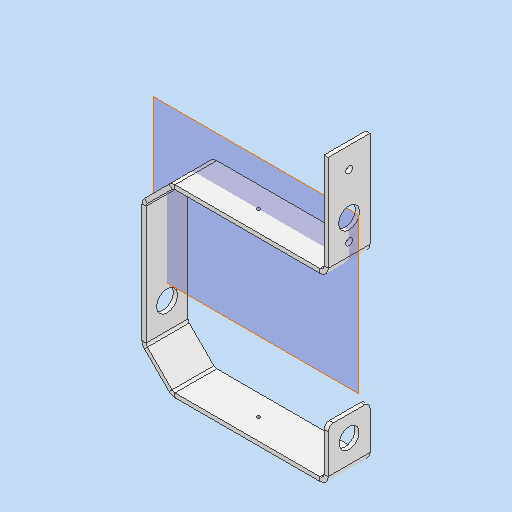
# Autodesk Inventor part: SE0004AN000_G01_106
Saved by Autodesk Inventor 2023.3 (Build 273359000, 359)
## iProperties
RuleStatus: InUse
Created: 2021-06-29
Part Number: SE0004AN000_G01_106
Material: 1.0330 DC01
Description: =<RBPARTNOTITLE2>
Document SubType Name: Blech
Designer: frt9bw
Mass: 758.691 g
Surface Area: 546.469 cm^2
Volume: 96.6485 cm^3
Density: 7.85 g/cm^3
Sheet Metal Rule: Standard_mm
Appearance: weiss AnP
Flat Pattern Width: 4 cm
Flat Pattern Length: 62.7681 cm
Flat Pattern Area: 251.073 cm^2
Sheet Metal Width: 40,000 mm
Sheet Metal Length: 627,681 mm
Sheet Metal Area: 25107,259 mm^2
Vendor: ASW
AnP_Kategorie: 1
AnP_Material: =<Material>
MaxAbmaße: 212,569 x 40 x 178,284 (FM)
AnP_TemplVers: 20200821
RBDOCUMENTTYPE: DRF
RBDOCUMENTVERSION: 00
RBDRAWINGMAINSCALE: 1:1
RBDRAWINGMISSINGSPEC: --
RBDRAWINGVOLUME: --
RBDSV1: 0850
RBGBEDGESIN1: +0,5
RBGBEDGESIN2: +0,2
RBGBEDGESOUT1: -0,3
RBGBEDGESOUT2: -0,1
RBMATERIAL: =<Material>
RBMATMEETS: --
RBMATNO: =<Part Number>
RBPARTMADEOF: 212,569 x 40 x 178,284 (FM)
RBPARTNO: SIEHE MNR
RBPARTNOTITLE1: manufactured part
RBPARTNOTITLE2: Anfertigungsteil
RBPARTSAFETYINDICATOR: --
RBSURFACE: powder-coated RAL9016, IGP-Dura mix 331SA90160C00
RBSURFACE2: pulverbeschichtet RAL9016, IGP-Dura mix 331SA90160C00
RBZEDGESNORM: ISO13715:2002-06
RBZGENDIMCLASS: m
RBZGENDIMNORM: ISO 2768-1:1989-11
RBZGENGEOCLASS: H
RBZGENGEONORM: ISO 2768-2:1989-11
RBZSURFACENORM: ISO13D2:2002-02
RBZTOLERANCENORM: ISO 14405-1:2010-12
Author: frt9bw
Keywords: =<RBPARTMADEOF>
Comments: =<RBSURFACE2>
Revision Number: 01
Autodesk Inventor part; units mm, degrees
ref_plane "YZ Plane" through (0, 0, 0) normal (1, 0, 0) x (0, 1, 0)
ref_plane "XY Plane" through (0, 0, 0) normal (0, 0, 1) x (1, 0, 0)
sketch "Skizze1" plane through (0, 0, 0) normal (0, 0, 1) x (1, 0, 0)
  line L0 (0, 0) -> (150, 0)
  line L1 (150, 0) -> (150, 40)
  line L2 (150, 40) -> (0, 40)
  line L3 (0, 40) -> (0, 0)
  dimension "d0" = 150
  dimension "d1" = 40
  measures "d0" distance of L1.end L2.end
  measures "d1" distance of L2.end L0.start
extrude "Grobblech1" add sketch "Skizze1" along normal blind 4
sketch "Skizze2" plane through (146, 40, 0) normal (1, 0, 0) x (0, 1, 0)
  line L0 (-40, 0) -> (0, 0)
  line L1 (0, 0) -> (0, 100)
  line L2 (0, 100) -> (-40, 100)
  line L3 (-40, 100) -> (-40, 0)
  constraints: 6 end point, 1 horizontal, 1 perpendicular, 1 vertical
edge flange "Lasche1" height 100 angle 90 thickness 4 bend radius 4 thickness toward (1, 0, 0) relief tear relief width 4 relief depth 2 edges at (150, 20, 4) wall of the first edge with corners at (146, 0, 0) (146, 40, 0) (146, 40, 100) (146, 0, 100)
bend "Biegung1"
corner "Ecke1"
sketch "Skizze3" plane through (2.8284, 40, 1.1716) normal (-0.7071068, 0, 0.7071068) x (0, -1, 0)
  line L0 (40, 0) -> (0, 0)
  line L1 (0, 0) -> (0, -40)
  line L2 (0, -40) -> (40, -40)
  line L3 (40, -40) -> (40, 0)
  constraints: 6 end point, 1 horizontal, 1 perpendicular, 1 vertical
edge flange "Lasche2" height 40 angle 45 thickness 4 bend radius 4 thickness toward (-0.7071068, 0, 0.7071068) relief tear relief width 4 relief depth 2 edges at (0, 20, 0) wall of the first edge with corners at (2.8284, 0, 1.1716) (2.8284, 40, 1.1716) (-25.4558, 40, -27.1127) (-25.4558, 0, -27.1127)
bend "Biegung2"
corner "Ecke2"
sketch "Skizze4" plane through (-24.2843, 40, -24.2843) normal (-1, 0, 0) x (0, -1, 0)
  line L0 (40, 0) -> (0, 0)
  line L1 (0, 0) -> (0, -120)
  line L2 (0, -120) -> (40, -120)
  line L3 (40, -120) -> (40, 0)
  constraints: 6 end point, 1 horizontal, 1 perpendicular, 1 vertical
edge flange "Lasche3" height 120 angle 45 thickness 4 bend radius 4 thickness toward (-1, 0, 0) relief tear relief width 4 relief depth 2 edges at (-25.4558, 20, -27.1127) wall of the first edge with corners at (-24.2843, 0, -24.2843) (-24.2843, 40, -24.2843) (-24.2843, 40, -144.2843) (-24.2843, 0, -144.2843)
bend "Biegung3"
corner "Ecke3"
sketch "Skizze5" plane through (-25.4558, 40, -141.4558) normal (-0.7071068, 0, -0.7071068) x (0, -1, 0)
  line L0 (40, 0) -> (0, 0)
  line L1 (0, 0) -> (0, -40)
  line L2 (0, -40) -> (40, -40)
  line L3 (40, -40) -> (40, 0)
  constraints: 6 end point, 1 horizontal, 1 perpendicular, 1 vertical
edge flange "Lasche4" height 40 angle 45 thickness 4 bend radius 4 thickness toward (-0.7071068, 0, -0.7071068) relief tear relief width 4 relief depth 2 edges at (-24.2843, 20, -144.2843) wall of the first edge with corners at (-25.4558, 0, -141.4558) (-25.4558, 40, -141.4558) (2.8284, 40, -169.7401) (2.8284, 0, -169.7401)
bend "Biegung4"
corner "Ecke4"
sketch "Skizze6" plane through (0, 40, -168.5685) normal (0, 0, -1) x (-1, 0, 0)
  line L0 (0, -40) -> (0, 0)
  line L1 (0, 0) -> (-150, 0)
  line L2 (-150, 0) -> (-150, -40)
  line L3 (-150, -40) -> (0, -40)
  constraints: 6 end point, 1 horizontal, 1 perpendicular, 1 vertical
edge flange "Lasche5" height 150 angle 45 thickness 4 bend radius 4 thickness toward (0, 0, -1) relief tear relief width 4 relief depth 2 edges at (2.8284, 20, -169.7401) wall of the first edge with corners at (0, 0, -168.5685) (0, 40, -168.5685) (150, 40, -168.5685) (150, 0, -168.5685)
bend "Biegung5"
corner "Ecke5"
sketch "Skizze7" plane through (146, 40, -172.5685) normal (1, 0, 0) x (0, 1, 0)
  line L0 (-40, 0) -> (0, 0)
  line L1 (0, 0) -> (0, 50)
  line L2 (0, 50) -> (-40, 50)
  line L3 (-40, 50) -> (-40, 0)
  constraints: 6 end point, 1 horizontal, 1 perpendicular, 1 vertical
edge flange "Lasche6" height 50 angle 90 thickness 4 bend radius 4 thickness toward (1, 0, 0) relief tear relief width 4 relief depth 2 edges at (150, 20, -168.5685) wall of the first edge with corners at (146, 0, -172.5685) (146, 40, -172.5685) (146, 40, -122.5685) (146, 0, -122.5685)
bend "Biegung6"
corner "Ecke6"
ref_plane "Arbeitsebene1" through (0, 20, 0) normal (0, 1, 0) x (-1, 0, 0)
sketch "Skizze8" plane through (150, 0, -122.5685) normal (1, 0, 0) x (0, 0, -1)
  line L0 (42, 0) -> (42, 40) projected
  line L1 (0, 40) -> (42, 40) projected
  line L2 (0, 0) -> (0, 40) projected
  line L3 (42, 0) -> (0, 0) projected
  circle A0 centre (20, 20) radius 9.5
  point P0 (-122.5685, 0)
  dimension "d64" = 19
  dimension "d65" = 40
  dimension "d66" = 20
  constraints: 1 centre point
  measures "d64" diameter of A0
  measures "d65" distance between parallel lines of L3 L1
  measures "d66" distance from line of A0.centre L2
extrude "Extrusion1" cut sketch "Skizze8" against normal blind 10 contours A0
fillet "Rundung1" radius 5 2 edges at (148, 0, -122.5685) (148, 40, -122.5685)
sketch "Skizze13" plane through (146, 0, 100) normal (-1, 0, 0) x (0, 0, 1)
  line L0 (-92, 40) -> (-92, 0) projected
  line L1 (-92, 0) -> (0, 0) projected
  line L2 (0, 0) -> (0, 40) projected
  line L3 (-92, 40) -> (0, 40) projected
  circle A0 centre (-60, 20) radius 10
  point P0 (-100, 0)
  dimension "d102" = 20
  dimension "d103" = 20
  dimension "d104" = 60
  constraints: 1 centre point
  measures "d102" diameter of A0
  measures "d103" distance from line of A0.centre L3
  measures "d104" distance from line of L2 A0.centre
extrude "Extrusion3" cut sketch "Skizze13" against normal blind 10 contours A0
sketch "Skizze14" plane through (146, 0, 100) normal (-1, 0, 0) x (0, 0, 1)
  circle A0 centre (-60, 20) radius 10 projected
  line L0 (-92, 40) -> (-92, 0) projected
  line L1 (-92, 0) -> (0, 0) projected
  line L2 (0, 0) -> (0, 40) projected
  line L3 (-92, 40) -> (0, 40) projected
  point P0 (-100, 0)
  point P1 (-80, 20)
  point P2 (-20, 20)
  dimension "d107" = 20
  dimension "d108" = 40
  constraints: 2 horizontal alignment
  measures "d107" distance of A0.centre point (-80, 20)
  measures "d108" distance of point (-20, 20) A0.centre
hole "Bohrung1" at (146, 20, 20) at (146, 20, 80) direction (1, 0, 0) diameter 6.5 end through all
sketch "Skizze15" plane through (-28.2843, 0, -27.598) normal (-1, 0, 0) x (0, 0, 1)
  line L0 (-113.3726, 40) -> (-113.3726, 0) projected
  line L1 (0, 0) -> (-113.3726, 0) projected
  line L2 (0, 0) -> (0, 40) projected
  line L3 (-113.3726, 40) -> (0, 40) projected
  circle A0 centre (-88.3726, 20) radius 10
  point P0 (27.598, 0)
  dimension "d116" = 20
  dimension "d117" = 20
  dimension "d118" = 25
  constraints: 1 centre point
  measures "d116" diameter of A0
  measures "d117" distance from line of L3 A0.centre
  measures "d118" distance from line of A0.centre L0
extrude "Extrusion4" cut sketch "Skizze15" against normal blind 10 contours A0
sketch "Skizze16" plane through (3.3137, 0, -172.5685) normal (0, 0, -1) x (-1, 0, 0)
  line L0 (-138.6863, 40) -> (-138.6863, 0) projected
  line L1 (0, 0) -> (-138.6863, 0) projected
  line L2 (0, 0) -> (0, 40) projected
  line L3 (-138.6863, 40) -> (0, 40) projected
  point P0 (3.3137, 0)
  point P1 (-60, 20)
  dimension "d121" = 60
  dimension "d122" = 20
  measures "d121" distance from line of point (-60, 20) L2
  measures "d122" distance from line of point (-60, 20) L1
hole "Bohrung2" at (63.3137, 20, -172.5685) direction (0, 0, 1) diameter 3.242 end through all thread size "M4x0.7" designation "M4" class "6H" standard "ISO Metric profile"
equation "\"d114\" = Stärke"
equation "\"d2\" = Stärke"
equation "\"d3\" = BreiteBiegungsfreistellung"
equation "\"d4\" = TiefeBiegungsfreistellung"
equation "\"d5\" = MinimalRest"
equation "\"d6\" = Übergangsradius"
equation "\"d9\" = Biegeradius"
equation "\"d10\" = GrößeEckenfreistellung"
equation "\"d11\" = Abstandsgröße"
equation "\"d12\" = JacobiRadiusGröße"
equation "\"d13\" = BreiteBiegungsfreistellung"
equation "\"d14\" = TiefeBiegungsfreistellung"
equation "\"d15\" = MinimalRest"
equation "\"d16\" = Übergangsradius"
equation "\"d19\" = Biegeradius"
equation "\"d20\" = GrößeEckenfreistellung"
equation "\"d21\" = Abstandsgröße"
equation "\"d22\" = JacobiRadiusGröße"
equation "\"d23\" = BreiteBiegungsfreistellung"
equation "\"d24\" = TiefeBiegungsfreistellung"
equation "\"d25\" = MinimalRest"
equation "\"d26\" = Übergangsradius"
equation "\"d29\" = Biegeradius"
equation "\"d30\" = GrößeEckenfreistellung"
equation "\"d31\" = Abstandsgröße"
equation "\"d32\" = JacobiRadiusGröße"
equation "\"d33\" = BreiteBiegungsfreistellung"
equation "\"d34\" = TiefeBiegungsfreistellung"
equation "\"d35\" = MinimalRest"
equation "\"d36\" = Übergangsradius"
equation "\"d39\" = Biegeradius"
equation "\"d40\" = GrößeEckenfreistellung"
equation "\"d41\" = Abstandsgröße"
equation "\"d42\" = JacobiRadiusGröße"
equation "\"d43\" = BreiteBiegungsfreistellung"
equation "\"d44\" = TiefeBiegungsfreistellung"
equation "\"d45\" = MinimalRest"
equation "\"d46\" = Übergangsradius"
equation "\"d49\" = Biegeradius"
equation "\"d50\" = GrößeEckenfreistellung"
equation "\"d51\" = Abstandsgröße"
equation "\"d52\" = JacobiRadiusGröße"
equation "\"d53\" = BreiteBiegungsfreistellung"
equation "\"d54\" = TiefeBiegungsfreistellung"
equation "\"d55\" = MinimalRest"
equation "\"d56\" = Übergangsradius"
equation "\"d59\" = Biegeradius"
equation "\"d60\" = GrößeEckenfreistellung"
equation "\"d61\" = Abstandsgröße"
equation "\"d62\" = JacobiRadiusGröße"
equation "\"Biegeradius\" = Stärke"
equation "\"BreiteBiegungsfreistellung\" = Stärke"
equation "\"TiefeBiegungsfreistellung\" = 0.5 * Stärke"
equation "\"GrößeEckenfreistellung\" = 4 * Stärke"
equation "\"MinimalRest\" = 2 * Stärke"
equation "\"Übergangsradius\" = Biegeradius"
equation "\"JacobiRadiusGröße\" = Biegeradius"
equation "\"Abstandsgröße\" = Stärke"
equation "\"Stärke\" = 4"
